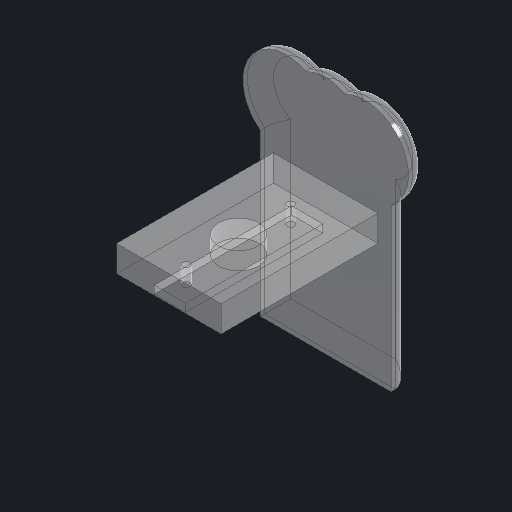
# Autodesk Inventor part: PEN-009R
Saved by Autodesk Inventor 2027.1 (Build 311270010, 270A)
## iProperties
Created: 2026-10-28
Part Number: PEN-009R
Material: PETG 3D Print
Description: Foot, right, PETG
Document SubType Name: Modeling
Designer: shyan
Mass: 14.0584 g
Surface Area: 63.8831 cm^2
Volume: 11.0696 cm^3
Density: 1.27 g/cm^3
Appearance: Polycarbonate - Clear
Author: shyan
Autodesk Inventor part; units mm, degrees
ref_plane "sk_sole_plane" through (0, 0, -64) normal (0, 0, 1) x (1, 0, 0)
sketch "sk_sole" plane through (0, 0, -64) normal (0, 0, 1) x (1, 0, 0)
  line L0 (0, 0) -> (70, 0) construction
  line L1 (0, 0) -> (0, 70) construction
  line L2 (11, -18) -> (41, -18)
  line L3 (41, -18) -> (41, 32)
  line L4 (41, 32) -> (11, 32)
  line L5 (11, 32) -> (11, -18)
  circle A0 centre (26, 27) radius 10
  circle A1 centre (35, 27) radius 10
  circle A2 centre (17, 27) radius 10
  dimension "d1" = 30
  dimension "d2" = 50
  dimension "d3" = 11
  dimension "d4" = 18
  dimension "d5" = 20
  dimension "d6" = 26
  dimension "d7" = 27
  dimension "d8" = 20
  dimension "d9" = 35
  dimension "d10" = 27
  dimension "d11" = 20
  dimension "d12" = 17
  dimension "d13" = 27
  constraints: 12 end point, 3 centre point, 2 parallel, 1 horizontal, 1 perpendicular, 4 other
  measures "d1" distance of L2.start L2.end
  measures "d2" distance of L2.end L3.end
  measures "d3" horizontal distance of L0.start L4.end
  measures "d4" vertical distance of L0.start L2.start
  measures "d5" diameter of A0
  measures "d6" horizontal distance of L0.start A0.centre
  measures "d7" vertical distance of L0.start A0.centre
  measures "d8" diameter of A1
  measures "d9" horizontal distance of L0.start A1.centre
  measures "d10" vertical distance of L0.start A1.centre
  measures "d11" diameter of A2
  measures "d12" horizontal distance of L0.start A2.centre
  measures "d13" vertical distance of L0.start A2.centre
extrude "Sole" add sketch "sk_sole" along normal blind 4
ref_plane "sk_bracket_plane" through (0, 0, -60) normal (0, 0, 1) x (1, 0, 0)
sketch "sk_bracket" plane through (0, 0, -60) normal (0, 0, 1) x (1, 0, 0)
  line L0 (0, 0) -> (70, 0) construction
  line L1 (0, 0) -> (0, 70) construction
  line L2 (14, 10) -> (38, 10)
  line L3 (38, 10) -> (38, 16)
  line L4 (38, 16) -> (14, 16)
  line L5 (14, 16) -> (14, 10)
  dimension "d17" = 24
  dimension "d18" = 6
  dimension "d19" = 14
  dimension "d20" = 10
  constraints: 12 end point, 2 parallel, 1 horizontal, 1 perpendicular, 4 other
  measures "d17" distance of L2.start L2.end
  measures "d18" distance of L2.end L3.end
  measures "d19" horizontal distance of L0.start L4.end
  measures "d20" vertical distance of L0.start L2.start
extrude "Bracket" add sketch "sk_bracket" along normal blind 36
ref_plane "sk_foot_horn_plane" through (0, 10, 0) normal (0, 1, 0) x (-1, 0, 0)
sketch "sk_foot_horn" plane through (0, 10, 0) normal (0, 1, 0) x (-1, 0, 0)
  line L0 (0, 0) -> (60, 0) construction
  line L1 (0, 0) -> (0, 60) construction
  line L2 (-29.6, -55.75) -> (-22.4, -55.75)
  line L3 (-22.4, -55.75) -> (-22.4, -24.25)
  line L4 (-22.4, -24.25) -> (-29.6, -24.25)
  line L5 (-29.6, -24.25) -> (-29.6, -55.75)
  dimension "d24" = 7.2
  dimension "d25" = 31.5
  dimension "d26" = 29.6
  dimension "d27" = 55.75
  constraints: 12 end point, 2 parallel, 1 horizontal, 1 perpendicular, 4 other
  measures "d24" distance of L2.start L2.end
  measures "d25" distance of L2.end L3.end
  measures "d26" horizontal distance of L0.start L4.end
  measures "d27" vertical distance of L0.start L2.start
extrude "HornPocket" cut sketch "sk_foot_horn" along normal blind 1.8
ref_plane "sk_foot_hub_plane" through (0, 11.8, 0) normal (0, 1, 0) x (-1, 0, 0)
sketch "sk_foot_hub" plane through (0, 11.8, 0) normal (0, 1, 0) x (-1, 0, 0)
  line L0 (0, 0) -> (60, 0) construction
  line L1 (0, 0) -> (0, 60) construction
  circle A0 centre (-26, -40) radius 4.6
  circle A1 centre (-26, -28) radius 0.85
  circle A2 centre (-26, -52) radius 0.85
  dimension "d31" = 9.2
  dimension "d32" = 26
  dimension "d33" = 40
  dimension "d34" = 1.7
  dimension "d35" = 26
  dimension "d36" = 28
  dimension "d37" = 1.7
  dimension "d38" = 26
  dimension "d39" = 52
  constraints: 4 end point, 3 centre point, 4 other
  measures "d31" diameter of A0
  measures "d32" horizontal distance of L0.start A0.centre
  measures "d33" vertical distance of L0.start A0.centre
  measures "d34" diameter of A1
  measures "d35" horizontal distance of L0.start A1.centre
  measures "d36" vertical distance of L0.start A1.centre
  measures "d37" diameter of A2
  measures "d38" horizontal distance of L0.start A2.centre
  measures "d39" vertical distance of L0.start A2.centre
extrude "HubAndHornScrews" cut sketch "sk_foot_hub" along normal blind 4
ref_plane "pl_hipX" through (26, 0, 0) normal (1, 0, 0) x (0, 1, 0)
ref_plane "pl_ankZ" through (0, 0, -40) normal (0, 0, 1) x (1, 0, 0)
fillet "SoleRocker" radius 3 6 edges at (43.4983, 32.2706, -64) (41, 0.5, -64) (26, -18, -64) (11, 0.5, -64) (8.5017, 32.2706, -64) (26, 37, -64)
equation "\"d1\" = foot_W"
equation "\"d2\" = foot_L"
equation "\"d3\" = hip_x - 0.5 * foot_W"
equation "\"d4\" = 0.5 * foot_L - foot_Yc"
equation "\"d5\" = toe_d"
equation "\"d6\" = hip_x"
equation "\"d7\" = toe_Y"
equation "\"d8\" = toe_d"
equation "\"d9\" = hip_x + toe_dx"
equation "\"d10\" = toe_Y"
equation "\"d11\" = toe_d"
equation "\"d12\" = hip_x - toe_dx"
equation "\"d13\" = toe_Y"
equation "\"d14\" = foot_T"
equation "\"d17\" = brk_W"
equation "\"d18\" = brk_T"
equation "\"d19\" = hip_x - 0.5 * brk_W"
equation "\"d20\" = brk_Yr"
equation "\"d21\" = brk_topz - foot_topz"
equation "\"d24\" = horn_hub"
equation "\"d25\" = horn_len"
equation "\"d26\" = hip_x + 0.5 * horn_hub"
equation "\"d27\" = -Z_ankle + 0.5 * horn_len"
equation "\"d28\" = horn_T"
equation "\"d31\" = horn_hub + hornhub_clr"
equation "\"d32\" = hip_x"
equation "\"d33\" = -Z_ankle"
equation "\"d34\" = m2_pilot"
equation "\"d35\" = hip_x"
equation "\"d36\" = -Z_ankle - horn_screw_z"
equation "\"d37\" = m2_pilot"
equation "\"d38\" = hip_x"
equation "\"d39\" = -Z_ankle + horn_screw_z"
equation "\"d40\" = hub_depth"
equation "\"d44\" = sole_rocker"
equation "\"clr\" = 0.3"
equation "\"wall\" = 2.4"
equation "\"sv_L\" = 22.8"
equation "\"sv_W\" = 12.2"
equation "\"sv_H\" = 22.7"
equation "\"sv_full\" = 28.5"
equation "\"sv_tab\" = 32.5"
equation "\"sv_tabT\" = 2.5"
equation "\"sv_tabZ\" = 15.5"
equation "\"sv_pitch\" = 27.5"
equation "\"sv_shaft\" = 5.9"
equation "\"sv_dome\" = 12"
equation "\"sv_domeH\" = 3.3"
equation "\"sv_spline\" = 4.8"
equation "\"m2_pilot\" = 1.7"
equation "\"horn_len\" = 31.5"
equation "\"horn_hub\" = 7.2"
equation "\"horn_tip\" = 4.5"
equation "\"horn_T\" = 1.8"
equation "\"horn_hubH\" = 3.8"
equation "\"ins_d\" = 4"
equation "\"ins_L\" = 6"
equation "\"m3\" = 3.4"
equation "\"nut_af\" = 5.8"
equation "\"hip_x\" = 26"
equation "\"plate_T\" = 5"
equation "\"col_H\" = 16"
equation "\"tray_T\" = 3"
equation "\"bodyW0\" = 96"
equation "\"bodyW35\" = 106"
equation "\"bodyD35\" = 86"
equation "\"bodyW85\" = 92"
equation "\"bodyD85\" = 74"
equation "\"bodyW112\" = 64"
equation "\"bodyD112\" = 56"
equation "\"Z_sec1\" = 35"
equation "\"Z_sec2\" = 85"
equation "\"Z_sec3\" = 112"
equation "\"Z_flip\" = 78"
equation "\"Z_bridge\" = 98"
equation "\"bat_W\" = 77"
equation "\"bat_D\" = 41"
equation "\"bat_H\" = 21"
equation "\"esp_W\" = 55"
equation "\"esp_D\" = 28"
equation "\"esp_H\" = 13"
equation "\"pcb_D\" = 38"
equation "\"pcb_T\" = 1.6"
equation "\"bk_D\" = 22"
equation "\"df_W\" = 49"
equation "\"df_D\" = 32"
equation "\"df_H\" = 12"
equation "\"sw_W\" = 21"
equation "\"sw_D\" = 15"
equation "\"sw_H\" = 25"
equation "\"usb_cut_W\" = 12"
equation "\"usb_cut_H\" = 7"
equation "\"usb_pitch\" = 28"
equation "\"foot_W\" = 30"
equation "\"foot_L\" = 50"
equation "\"foot_T\" = 4"
equation "\"foot_Yc\" = 7"
equation "\"foot_topz\" = -60"
equation "\"toe_d\" = 20"
equation "\"toe_dx\" = 9"
equation "\"toe_Y\" = 27"
equation "\"brk_W\" = 24"
equation "\"brk_T\" = 6"
equation "\"brk_Yr\" = 10"
equation "\"brk_topz\" = -24"
equation "\"hornhub_clr\" = 2"
equation "\"horn_screw_z\" = 12"
equation "\"hub_depth\" = 4"
equation "\"Z_ankle\" = -40"
equation "\"foot_fil\" = 3"
equation "\"d0\" = foot_topz - foot_T"
equation "\"d30\" = brk_Yr + horn_T"
equation "\"hip_X\" = hip_x"
equation "\"d42\" = hip_X"
equation "\"sole_rocker\" = 3"
body "Solid1"
